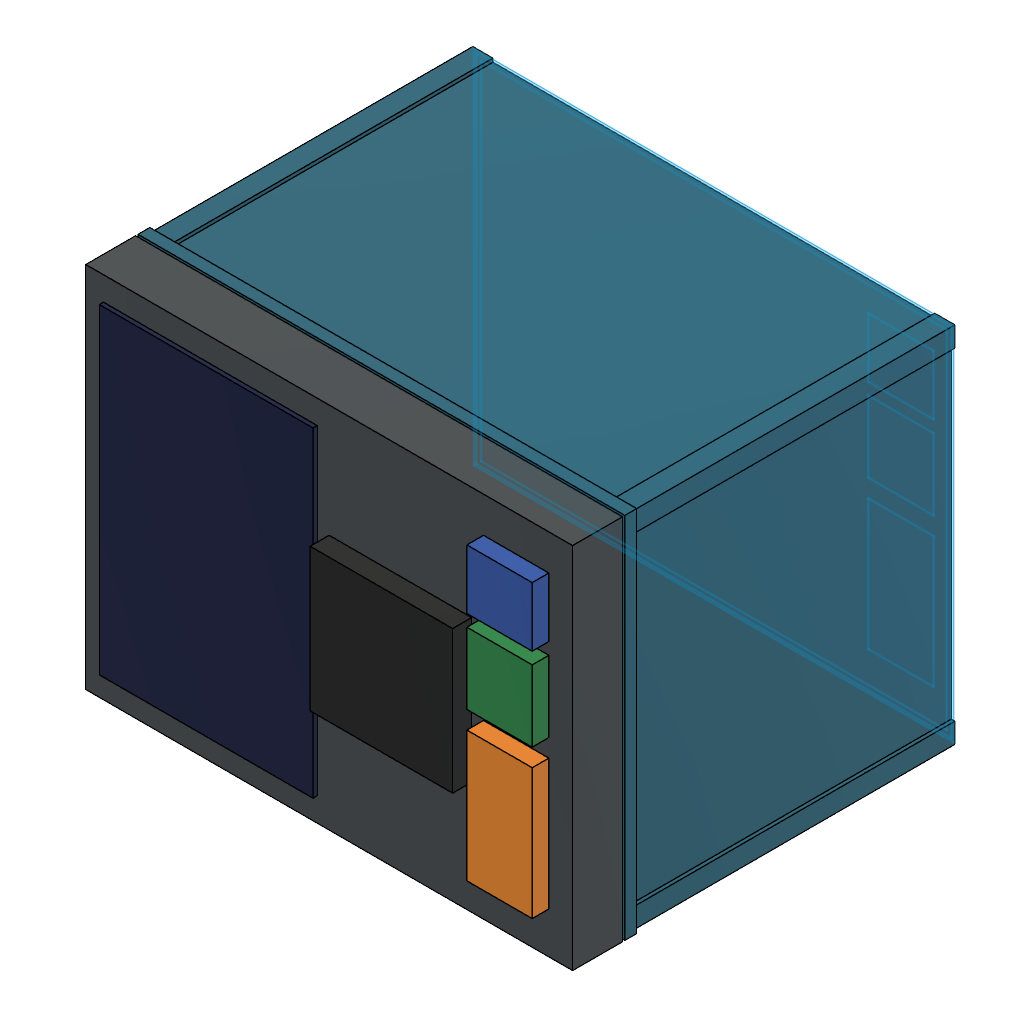
FrostChain_ESkin_Crate_v2 (Autodesk Fusion 360 design; units mm, degrees)
part number: 2026-10-19-23-57-47-023
part number: 2026-10-19-23-57-47-727
part number: 2026-10-19-23-57-48-551
part number: 2026-10-19-23-57-48-696
part number: 2026-10-19-23-57-48-926
part number: 2026-10-19-23-57-49-133
part number: 2026-10-19-23-57-49-841
Autodesk Fusion 360 part; units mm, degrees
sketch "Sketch_Outer_Crate_Footprint" plane through (0, 0, 0) normal (0, 0, 1) x (1, 0, 0) in component "01_Outer_HDPE_Structural_Shell"
  line L0 (200, 150) -> (-200, 150)
  line L1 (-200, 150) -> (-200, -150)
  line L2 (-200, -150) -> (200, -150)
  line L3 (200, -150) -> (200, 150)
extrude "Extrude1" add sketch "Sketch_Outer_Crate_Footprint" along normal blind 280 makes body 1 in component "01_Outer_HDPE_Structural_Shell"
sketch "Sketch_Inner_Shell_Cavity" plane through (0, 0, 0) normal (0, 0, 1) x (1, 0, 0) in component "01_Outer_HDPE_Structural_Shell"
  line L0 (196, 146) -> (-196, 146)
  line L1 (-196, 146) -> (-196, -146)
  line L2 (-196, -146) -> (196, -146)
  line L3 (196, -146) -> (196, 146)
extrude "Extrude2" cut sketch "Sketch_Inner_Shell_Cavity" along normal blind 280 from surface at 4 bodies 1 in component "01_Outer_HDPE_Structural_Shell"
sketch "Sketch_Corner_Stacking_Pilasters" plane through (0, 0, 0) normal (0, 0, 1) x (1, 0, 0) in component "01_Outer_HDPE_Structural_Shell"
  line L0 (-186, -136) -> (-203, -136)
  line L1 (-203, -136) -> (-203, -153)
  line L2 (-203, -153) -> (-186, -153)
  line L3 (-186, -153) -> (-186, -136)
  line L4 (-186, 136) -> (-203, 136)
  line L5 (-203, 136) -> (-203, 153)
  line L6 (-203, 153) -> (-186, 153)
  line L7 (-186, 153) -> (-186, 136)
  line L8 (186, -136) -> (203, -136)
  line L9 (203, -136) -> (203, -153)
  line L10 (203, -153) -> (186, -153)
  line L11 (186, -153) -> (186, -136)
  line L12 (186, 136) -> (203, 136)
  line L13 (203, 136) -> (203, 153)
  line L14 (203, 153) -> (186, 153)
  line L15 (186, 153) -> (186, 136)
extrude "Extrude3" add sketch "Sketch_Corner_Stacking_Pilasters" along normal blind 280 contours L0 L1 L2 L3 bodies 1 in component "01_Outer_HDPE_Structural_Shell"
extrude "Extrude4" add sketch "Sketch_Corner_Stacking_Pilasters" along normal blind 280 contours L12 L13 L14 L15 bodies 1 in component "01_Outer_HDPE_Structural_Shell"
extrude "Extrude5" add sketch "Sketch_Corner_Stacking_Pilasters" along normal blind 280 contours L4 L5 L6 L7 bodies 1 in component "01_Outer_HDPE_Structural_Shell"
extrude "Extrude6" add sketch "Sketch_Corner_Stacking_Pilasters" along normal blind 280 contours L8 L9 L10 L11 bodies 1 in component "01_Outer_HDPE_Structural_Shell"
sketch "Sketch_Top_Rim_Seal_Land" plane through (0, 0, 0) normal (0, 0, 1) x (1, 0, 0) in component "01_Outer_HDPE_Structural_Shell"
  line L0 (205, 155) -> (-205, 155)
  line L1 (-205, 155) -> (-205, -155)
  line L2 (-205, -155) -> (205, -155)
  line L3 (205, -155) -> (205, 155)
  line L4 (184, 134) -> (-184, 134)
  line L5 (-184, 134) -> (-184, -134)
  line L6 (-184, -134) -> (184, -134)
  line L7 (184, -134) -> (184, 134)
extrude "Extrude7" add sketch "Sketch_Top_Rim_Seal_Land" along normal blind 10 from surface at 270 bodies 1 in component "01_Outer_HDPE_Structural_Shell"
sketch "Sketch_VIP_EPS_Liner" plane through (0, 0, 0) normal (0, 0, 1) x (1, 0, 0) in component "02_EPS_VIP_Insulation_Core"
  line L0 (196, 146) -> (-196, 146)
  line L1 (-196, 146) -> (-196, -146)
  line L2 (-196, -146) -> (196, -146)
  line L3 (196, -146) -> (196, 146)
extrude "Extrude1'" add sketch "Sketch_VIP_EPS_Liner" along normal blind 266 from surface at 4 separate body makes body 2 in component "02_EPS_VIP_Insulation_Core"
sketch "Sketch_VIP_Inner_Cargo_Void" plane through (0, 0, 0) normal (0, 0, 1) x (1, 0, 0) in component "02_EPS_VIP_Insulation_Core"
  line L0 (171, 121) -> (-171, 121)
  line L1 (-171, 121) -> (-171, -121)
  line L2 (-171, -121) -> (171, -121)
  line L3 (171, -121) -> (171, 121)
extrude "Extrude2'" cut sketch "Sketch_VIP_Inner_Cargo_Void" along normal blind 280 from surface at 29 bodies 2 in component "02_EPS_VIP_Insulation_Core"
sketch "Sketch_4C_PCM_Wall_Cassettes" plane through (0, 0, 0) normal (0, 0, 1) x (1, 0, 0) in component "03_PCM_4C_Cold_Packs"
  line L0 (-165, 105) -> (165, 105)
  line L1 (165, 105) -> (165, 120)
  line L2 (165, 120) -> (-165, 120)
  line L3 (-165, 120) -> (-165, 105)
  line L4 (-165, -120) -> (165, -120)
  line L5 (165, -120) -> (165, -105)
  line L6 (165, -105) -> (-165, -105)
  line L7 (-165, -105) -> (-165, -120)
  line L8 (-170, -101) -> (-155, -101)
  line L9 (-155, -101) -> (-155, 101)
  line L10 (-155, 101) -> (-170, 101)
  line L11 (-170, 101) -> (-170, -101)
  line L12 (155, -101) -> (170, -101)
  line L13 (170, -101) -> (170, 101)
  line L14 (170, 101) -> (155, 101)
  line L15 (155, 101) -> (155, -101)
extrude "Extrude1''" add sketch "Sketch_4C_PCM_Wall_Cassettes" along normal blind 222 from surface at 33 separate body contours L0 L1 L2 L3 makes body 3 in component "03_PCM_4C_Cold_Packs"
extrude "Extrude2''" add sketch "Sketch_4C_PCM_Wall_Cassettes" along normal blind 222 from surface at 33 separate body contours L8 L9 L10 L11 makes body 4 in component "03_PCM_4C_Cold_Packs"
extrude "Extrude3'" add sketch "Sketch_4C_PCM_Wall_Cassettes" along normal blind 222 from surface at 33 separate body contours L4 L5 L6 L7 makes body 5 in component "03_PCM_4C_Cold_Packs"
extrude "Extrude4'" add sketch "Sketch_4C_PCM_Wall_Cassettes" along normal blind 222 from surface at 33 separate body contours L12 L13 L14 L15 makes body 6 in component "03_PCM_4C_Cold_Packs"
sketch "Sketch_Active_Graphite_Trace" plane through (0, 0, 0) normal (0, 0, 1) x (1, 0, 0) in component "04_Graphite_ESkin_HalfBridge"
  line L0 (202, 152) -> (-202, 152)
  line L1 (-202, 152) -> (-202, -152)
  line L2 (-202, -152) -> (202, -152)
  line L3 (202, -152) -> (202, 152)
  line L4 (196, 146) -> (-196, 146)
  line L5 (-196, 146) -> (-196, -146)
  line L6 (-196, -146) -> (196, -146)
  line L7 (196, -146) -> (196, 146)
extrude "Extrude1'''" add sketch "Sketch_Active_Graphite_Trace" along normal blind 2 from surface at 280 separate body makes body 7 in component "04_Graphite_ESkin_HalfBridge"
sketch "Sketch_Dummy_Compensation_Trace" plane through (0, 0, 0) normal (0, 0, 1) x (1, 0, 0) in component "04_Graphite_ESkin_HalfBridge"
  line L0 (194, 144) -> (-194, 144)
  line L1 (-194, 144) -> (-194, -144)
  line L2 (-194, -144) -> (194, -144)
  line L3 (194, -144) -> (194, 144)
  line L4 (188, 138) -> (-188, 138)
  line L5 (-188, 138) -> (-188, -138)
  line L6 (-188, -138) -> (188, -138)
  line L7 (188, -138) -> (188, 138)
extrude "Extrude2'''" add sketch "Sketch_Dummy_Compensation_Trace" along normal blind 2 from surface at 280 separate body makes body 8 in component "04_Graphite_ESkin_HalfBridge"
sketch "Sketch_ColdSide_HeatSink_6061" plane through (0, 0, 0) normal (0, 0, 1) x (1, 0, 0) in component "05_Peltier_TEC1_12706_Thermal_Engine"
  line L0 (0, -60) -> (120, -60)
  line L1 (120, -60) -> (120, 60)
  line L2 (120, 60) -> (0, 60)
  line L3 (0, 60) -> (0, -60)
extrude "Extrude1''''" add sketch "Sketch_ColdSide_HeatSink_6061" along normal blind 8 from surface at 272 separate body makes body 9 in component "05_Peltier_TEC1_12706_Thermal_Engine"
sketch "Sketch_ColdSide_Extruded_Fins" plane through (0, 0, 0) normal (0, 0, 1) x (1, 0, 0) in component "05_Peltier_TEC1_12706_Thermal_Engine"
  line L0 (5, -53) -> (115, -53)
  line L1 (115, -53) -> (115, -47)
  line L2 (115, -47) -> (5, -47)
  line L3 (5, -47) -> (5, -53)
  line L4 (5, -33) -> (115, -33)
  line L5 (115, -33) -> (115, -27)
  line L6 (115, -27) -> (5, -27)
  line L7 (5, -27) -> (5, -33)
  line L8 (5, -13) -> (115, -13)
  line L9 (115, -13) -> (115, -7)
  line L10 (115, -7) -> (5, -7)
  line L11 (5, -7) -> (5, -13)
  line L12 (5, 7) -> (115, 7)
  line L13 (115, 7) -> (115, 13)
  line L14 (115, 13) -> (5, 13)
  line L15 (5, 13) -> (5, 7)
  line L16 (5, 27) -> (115, 27)
  line L17 (115, 27) -> (115, 33)
  line L18 (115, 33) -> (5, 33)
  line L19 (5, 33) -> (5, 27)
  line L20 (5, 47) -> (115, 47)
  line L21 (115, 47) -> (115, 53)
  line L22 (115, 53) -> (5, 53)
  line L23 (5, 53) -> (5, 47)
extrude "Extrude2''''" add sketch "Sketch_ColdSide_Extruded_Fins" along normal blind 18 from surface at 254 contours L0 L1 L2 L3 bodies 9 in component "05_Peltier_TEC1_12706_Thermal_Engine"
extrude "Extrude3''" add sketch "Sketch_ColdSide_Extruded_Fins" along normal blind 18 from surface at 254 contours L12 L13 L14 L15 bodies 9 in component "05_Peltier_TEC1_12706_Thermal_Engine"
extrude "Extrude4''" add sketch "Sketch_ColdSide_Extruded_Fins" along normal blind 18 from surface at 254 contours L8 L9 L10 L11 bodies 9 in component "05_Peltier_TEC1_12706_Thermal_Engine"
extrude "Extrude5'" add sketch "Sketch_ColdSide_Extruded_Fins" along normal blind 18 from surface at 254 contours L16 L17 L18 L19 bodies 9 in component "05_Peltier_TEC1_12706_Thermal_Engine"
extrude "Extrude6'" add sketch "Sketch_ColdSide_Extruded_Fins" along normal blind 18 from surface at 254 contours L4 L5 L6 L7 bodies 9 in component "05_Peltier_TEC1_12706_Thermal_Engine"
extrude "Extrude7'" add sketch "Sketch_ColdSide_Extruded_Fins" along normal blind 18 from surface at 254 contours L20 L21 L22 L23 bodies 9 in component "05_Peltier_TEC1_12706_Thermal_Engine"
sketch "Sketch_TEC1_12706_Peltier" plane through (0, 0, 0) normal (0, 0, 1) x (1, 0, 0) in component "05_Peltier_TEC1_12706_Thermal_Engine"
  line L0 (40, -20) -> (80, -20)
  line L1 (80, -20) -> (80, 20)
  line L2 (80, 20) -> (40, 20)
  line L3 (40, 20) -> (40, -20)
extrude "Extrude8" add sketch "Sketch_TEC1_12706_Peltier" along normal blind 12 from surface at 282 separate body makes body 10 in component "05_Peltier_TEC1_12706_Thermal_Engine"
sketch "Sketch_HotSide_Reject_HeatSink" plane through (0, 0, 0) normal (0, 0, 1) x (1, 0, 0) in component "05_Peltier_TEC1_12706_Thermal_Engine"
  line L0 (0, -60) -> (120, -60)
  line L1 (120, -60) -> (120, 60)
  line L2 (120, 60) -> (0, 60)
  line L3 (0, 60) -> (0, -60)
extrude "Extrude9" add sketch "Sketch_HotSide_Reject_HeatSink" along normal blind 16 from surface at 324 separate body makes body 11 in component "05_Peltier_TEC1_12706_Thermal_Engine"
sketch "Sketch_Retrofit_Lid_Body" plane through (0, 0, 0) normal (0, 0, 1) x (1, 0, 0) in component "06_Retrofit_Solar_Lid_And_FPGA_Bay"
  line L0 (205, 155) -> (-205, 155)
  line L1 (-205, 155) -> (-205, -155)
  line L2 (-205, -155) -> (205, -155)
  line L3 (205, -155) -> (205, 155)
extrude "Extrude1'''''" add sketch "Sketch_Retrofit_Lid_Body" along normal blind 42 from surface at 282 separate body makes body 12 in component "06_Retrofit_Solar_Lid_And_FPGA_Bay"
sketch "Sketch_30W_Flexible_Solar_PV" plane through (0, 0, 0) normal (0, 0, 1) x (1, 0, 0) in component "06_Retrofit_Solar_Lid_And_FPGA_Bay"
  line L0 (-190, -135) -> (-10, -135)
  line L1 (-10, -135) -> (-10, 135)
  line L2 (-10, 135) -> (-190, 135)
  line L3 (-190, 135) -> (-190, -135)
extrude "Extrude2'''''" add sketch "Sketch_30W_Flexible_Solar_PV" along normal blind 3.5 from surface at 324 separate body makes body 13 in component "06_Retrofit_Solar_Lid_And_FPGA_Bay"
sketch "Sketch_IP65_Electronics_And_Battery_Bay" plane through (0, 0, 0) normal (0, 0, 1) x (1, 0, 0) in component "06_Retrofit_Solar_Lid_And_FPGA_Bay"
  line L0 (130, -120) -> (185, -120)
  line L1 (185, -120) -> (185, -10)
  line L2 (185, -10) -> (130, -10)
  line L3 (130, -10) -> (130, -120)
  line L4 (130, 5) -> (185, 5)
  line L5 (185, 5) -> (185, 65)
  line L6 (185, 65) -> (130, 65)
  line L7 (130, 65) -> (130, 5)
  line L8 (130, 75) -> (185, 75)
  line L9 (185, 75) -> (185, 125)
  line L10 (185, 125) -> (130, 125)
  line L11 (130, 125) -> (130, 75)
extrude "Extrude3'''" add sketch "Sketch_IP65_Electronics_And_Battery_Bay" along normal blind 14 from surface at 324 separate body contours L0 L1 L2 L3 makes body 14 in component "06_Retrofit_Solar_Lid_And_FPGA_Bay"
extrude "Extrude4'''" add sketch "Sketch_IP65_Electronics_And_Battery_Bay" along normal blind 14 from surface at 324 separate body contours L4 L5 L6 L7 makes body 15 in component "06_Retrofit_Solar_Lid_And_FPGA_Bay"
extrude "Extrude5''" add sketch "Sketch_IP65_Electronics_And_Battery_Bay" along normal blind 14 from surface at 324 separate body contours L8 L9 L10 L11 makes body 16 in component "06_Retrofit_Solar_Lid_And_FPGA_Bay"
component "01_Outer_HDPE_Structural_Shell" placed x (1, 0, 0) y (0, 1, 0) z (0, 0, 1) at (0, 0, 0)
component "02_EPS_VIP_Insulation_Core" placed x (1, 0, 0) y (0, 1, 0) z (0, 0, 1) at (0, 0, 0)
component "03_PCM_4C_Cold_Packs" placed x (1, 0, 0) y (0, 1, 0) z (0, 0, 1) at (0, 0, 0)
component "04_Graphite_ESkin_HalfBridge" placed x (1, 0, 0) y (0, 1, 0) z (0, 0, 1) at (0, 0, 0)
component "05_Peltier_TEC1_12706_Thermal_Engine" placed x (1, 0, 0) y (0, 1, 0) z (0, 0, 1) at (0, 0, 0)
component "06_Retrofit_Solar_Lid_And_FPGA_Bay" placed x (1, 0, 0) y (0, 1, 0) z (0, 0, 1) at (0, 0, 0)
equation "Crate_Length = 400 mm" comment "Standard first-mile crate outer length"
equation "Crate_Width = 300 mm" comment "Standard first-mile crate outer width"
equation "Crate_Height = 280 mm" comment "Crate body height"
equation "HDPE_Wall = 4 mm" comment "Outer structural HDPE wall thickness"
equation "VIP_EPS_Thick = 25 mm" comment "EPS + VIP thermal insulation thickness"
equation "PCM_Thick = 16 mm" comment "4.5C Phase Change Material pack thickness"
equation "Lid_Height = 42 mm" comment "Retrofit Solar + Peltier top lid thickness"
named bodies: "HDPE_Crate_Body", "EPS_VIP_Composite_Core", "PCM_4C_Cassette_1", "PCM_4C_Cassette_2", "PCM_4C_Cassette_3", "PCM_4C_Cassette_4", "Graphite_Active_Strain_Trace", "Graphite_Dummy_Ref_Trace", "ColdSide_6061_FinBlock", "TEC1_12706_Peltier_Module", "HotSide_6061_RejectSink", "Retrofit_Insulated_Lid", "Flexible_30W_Solar_Panel", "LiFePO4_12V_6Ah_BMS_Pack", "TangNano9K_FPGA_SigmaDelta_PCB", "ESP32_S3_5G_GPS_Module"
